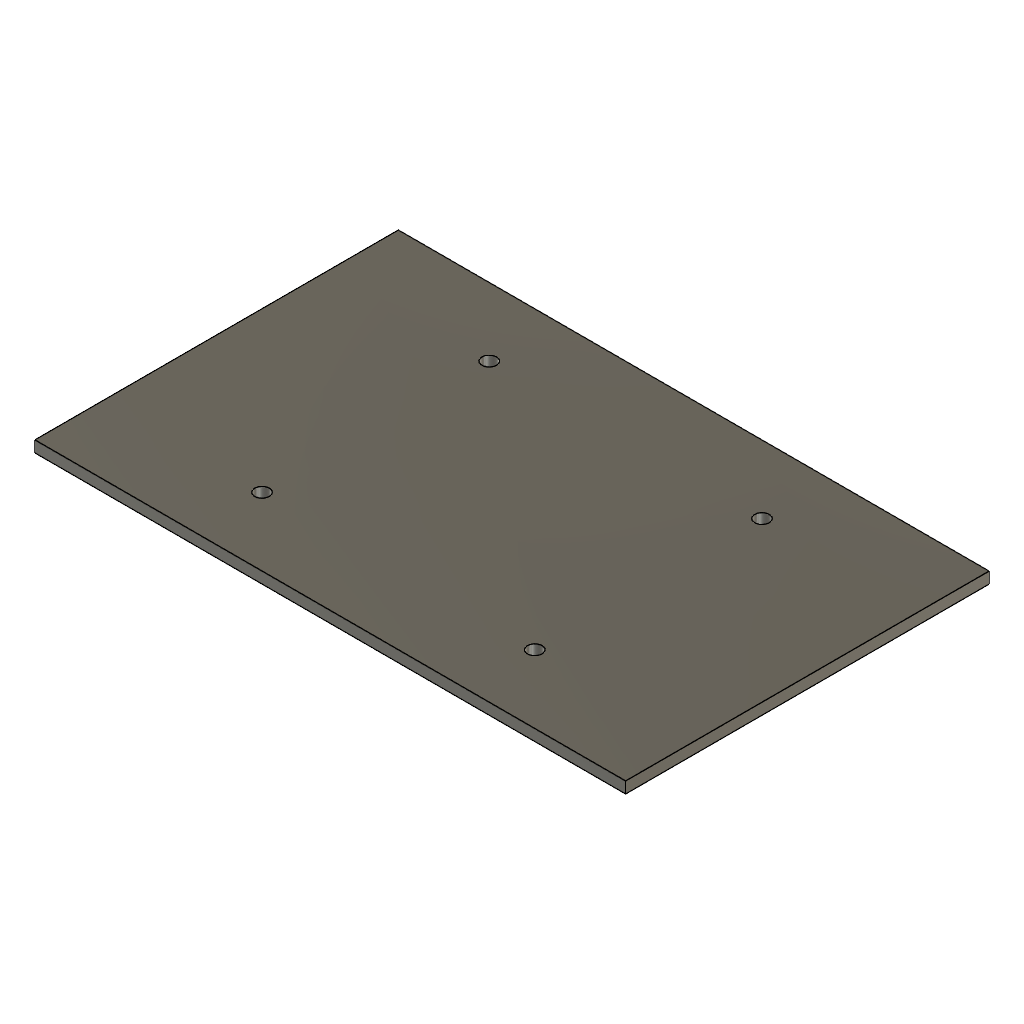
Controlled Traffic System - Vehicle Unit (Autodesk Fusion 360 archive; units mm, degrees)
design "Mounting Deck"
part number: 2026-10-08-00-01-35-748
Autodesk Fusion 360 part; units mm, degrees
ref_plane "WorkPlane2" through (0, 0, 28) normal (0, 0, 1) x (1, 0, 0)
sketch "01 - Enlarged Mounting Deck Profile" plane through (0, 0, 28) normal (0, 0, 1) x (1, 0, 0)
  line L0 (-65, -40) -> (65, -40)
  line L1 (65, -40) -> (65, 40)
  line L2 (65, 40) -> (-65, 40)
  line L3 (-65, 40) -> (-65, -40)
  circle A0 centre (-30, -25) radius 1.6
  circle A1 centre (30, -25) radius 1.6
  circle A2 centre (-30, 25) radius 1.6
  circle A3 centre (30, 25) radius 1.6
extrude "02 - Enlarged Mounting Deck" add sketch "01 - Enlarged Mounting Deck Profile" along normal blind 2.5

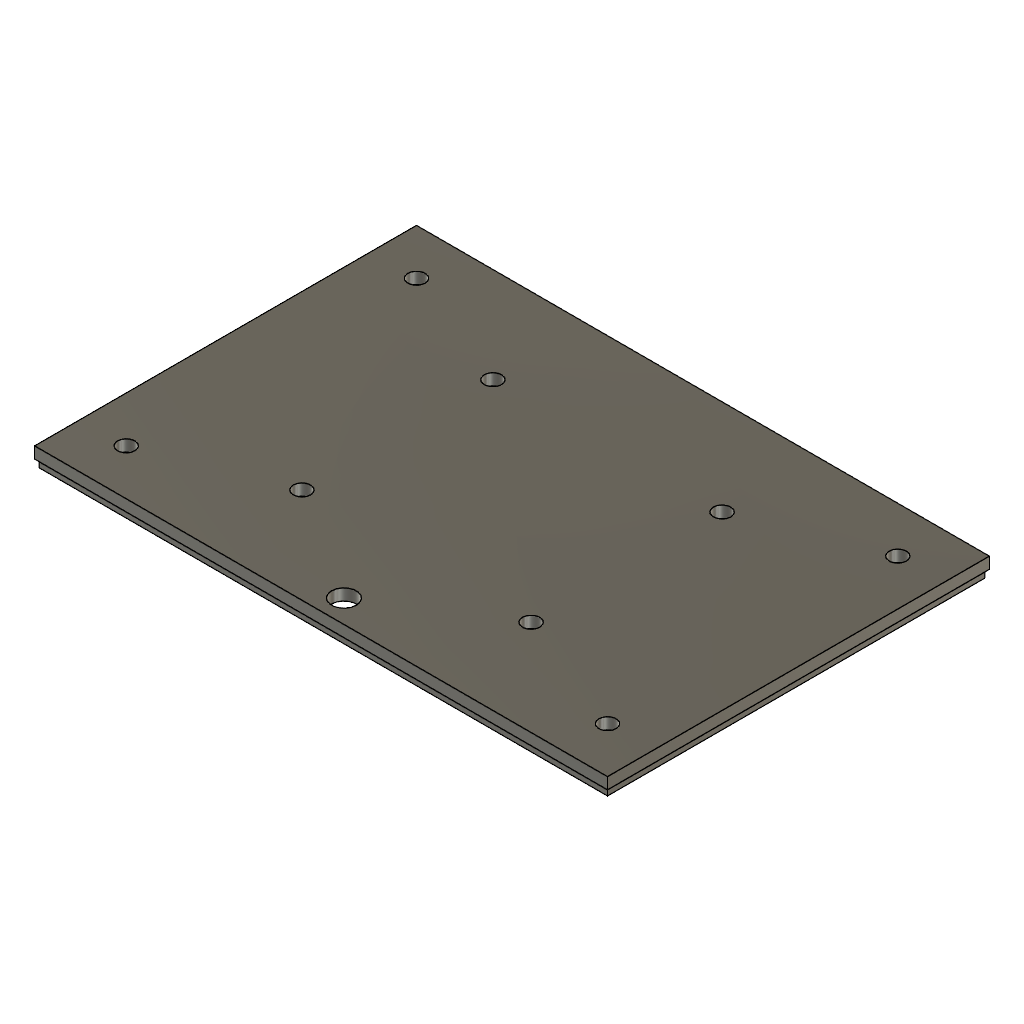
design "Enclosure Lid"
part number: 2026-10-07-13-07-07-370
Autodesk Fusion 360 part; units mm, degrees
ref_plane "WorkPlane1" through (0, 0, 32) normal (0, 0, 1) x (1, 0, 0)
sketch "01 - Lid Base Sketch" plane through (0, 0, 32) normal (0, 0, 1) x (1, 0, 0)
  line L0 (-75, -50) -> (75, -50)
  line L1 (75, -50) -> (75, 50)
  line L2 (75, 50) -> (-75, 50)
  line L3 (-75, 50) -> (-75, -50)
extrude "02 - Lid Plate" add sketch "01 - Lid Base Sketch" along normal blind 3
sketch "03 - Lid Seating Lip Sketch" plane through (0, 0, 32) normal (0, 0, 1) x (1, 0, 0)
  line L0 (-74.4, -49.4) -> (74.4, -49.4)
  line L1 (74.4, -49.4) -> (74.4, 49.4)
  line L2 (74.4, 49.4) -> (-74.4, 49.4)
  line L3 (-74.4, 49.4) -> (-74.4, -49.4)
  line L4 (-72.4, -47.4) -> (72.4, -47.4)
  line L5 (72.4, -47.4) -> (72.4, 47.4)
  line L6 (72.4, 47.4) -> (-72.4, 47.4)
  line L7 (-72.4, 47.4) -> (-72.4, -47.4)
extrude "04 - Lid Seating Lip" add sketch "03 - Lid Seating Lip Sketch" against normal blind 2
sketch "05 - Lid Screw Holes 8 Positions" plane through (0, 0, 32) normal (0, 0, 1) x (1, 0, 0)
  circle A0 centre (-63, -38) radius 2.25
  circle A1 centre (63, -38) radius 2.25
  circle A2 centre (-30, -25) radius 2.25
  circle A3 centre (30, -25) radius 2.25
  circle A4 centre (-30, 25) radius 2.25
  circle A5 centre (30, 25) radius 2.25
  circle A6 centre (-63, 38) radius 2.25
  circle A7 centre (63, 38) radius 2.25
extrude "06 - Lid Screw Hole 1" cut sketch "05 - Lid Screw Holes 8 Positions" along normal blind 3 contours A0
extrude "06 - Lid Screw Hole 2" cut sketch "05 - Lid Screw Holes 8 Positions" along normal blind 3 contours A4
extrude "06 - Lid Screw Hole 3" cut sketch "05 - Lid Screw Holes 8 Positions" along normal blind 3 contours A3
extrude "06 - Lid Screw Hole 4" cut sketch "05 - Lid Screw Holes 8 Positions" along normal blind 3 contours A5
extrude "06 - Lid Screw Hole 5" cut sketch "05 - Lid Screw Holes 8 Positions" along normal blind 3 contours A2
extrude "06 - Lid Screw Hole 6" cut sketch "05 - Lid Screw Holes 8 Positions" along normal blind 3 contours A6
extrude "06 - Lid Screw Hole 7" cut sketch "05 - Lid Screw Holes 8 Positions" along normal blind 3 contours A1
extrude "06 - Lid Screw Hole 8" cut sketch "05 - Lid Screw Holes 8 Positions" along normal blind 3 contours A7
sketch "07 - Cellular Antenna Hole" plane through (0, 0, 32) normal (0, 0, 1) x (1, 0, 0)
  circle A0 centre (0, -44) radius 3.25
extrude "08 - Cellular Antenna Pass-Through" cut sketch "07 - Cellular Antenna Hole" along normal blind 3

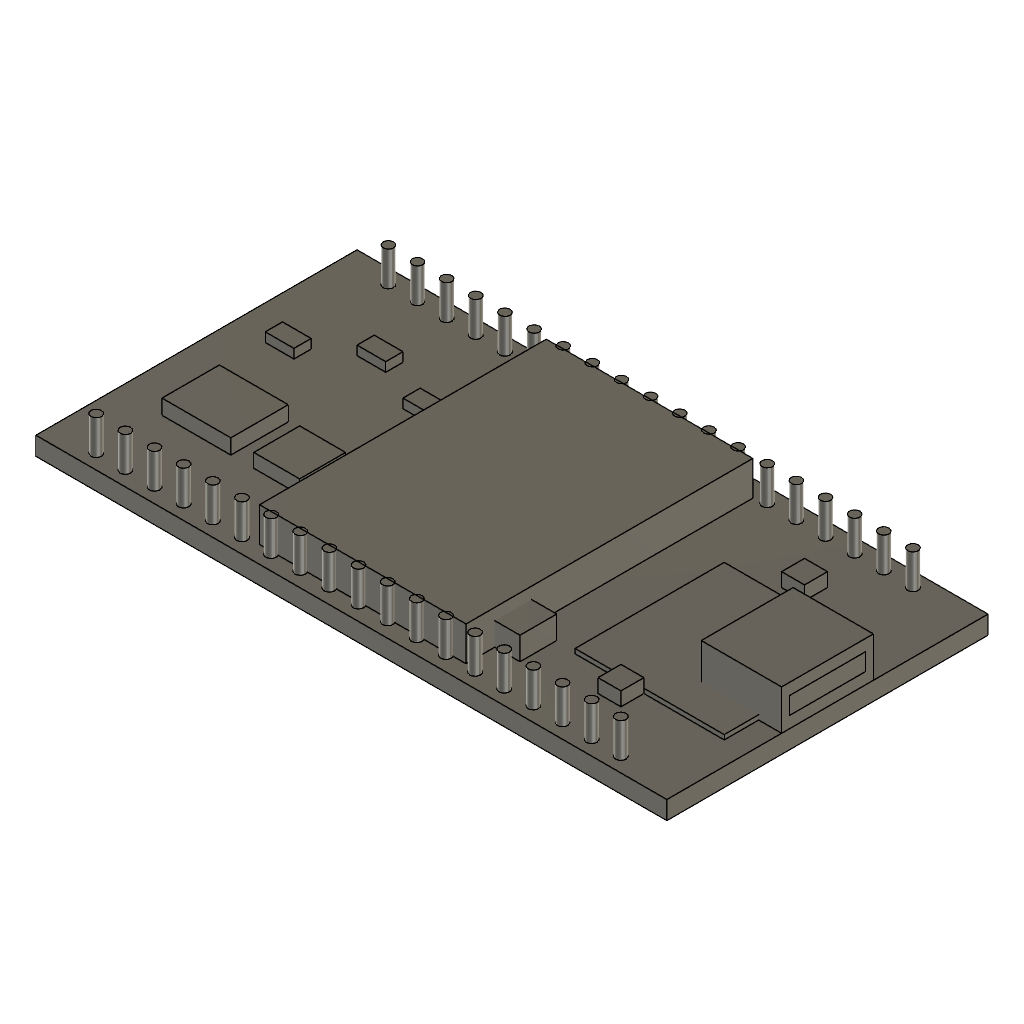
design "ESP32"
part number: 2026-10-08-00-19-46-799
Autodesk Fusion 360 part; units mm, degrees
ref_plane "WorkPlane1" through (0, 0, 30.5) normal (0, 0, 1) x (1, 0, 0)
sketch "01 - ESP32 DevKitC V4 PCB Sketch" plane through (0, 0, 30.5) normal (0, 0, 1) x (1, 0, 0)
  line L0 (-34.5, -9) -> (20.5, -9)
  line L1 (20.5, -9) -> (20.5, 19)
  line L2 (20.5, 19) -> (-34.5, 19)
  line L3 (-34.5, 19) -> (-34.5, -9)
extrude "01 - ESP32 DevKitC V4 PCB" add sketch "01 - ESP32 DevKitC V4 PCB Sketch" along normal blind 1.6 makes body 1
ref_plane "WorkPlane2" through (0, 0, 32.1) normal (0, 0, 1) x (1, 0, 0)
sketch "02 - ESP32-WROOM-32E Shield Sketch" plane through (0, 0, 32.1) normal (0, 0, 1) x (1, 0, 0)
  line L0 (-16.5, -7.5) -> (1.5, -7.5)
  line L1 (1.5, -7.5) -> (1.5, 17.5)
  line L2 (1.5, 17.5) -> (-16.5, 17.5)
  line L3 (-16.5, 17.5) -> (-16.5, -7.5)
extrude "02 - ESP32-WROOM-32E Shield" add sketch "02 - ESP32-WROOM-32E Shield Sketch" along normal blind 3 separate body makes body 2
ref_plane "WorkPlane3" through (0, 0, 32.1) normal (0, 0, 1) x (1, 0, 0)
sketch "Left Header Pin 01" plane through (0, 0, 32.1) normal (0, 0, 1) x (1, 0, 0)
  circle A0 centre (-30.5, -7.73) radius 0.45
extrude "03 - Left Header Pin 01" add sketch "Left Header Pin 01" along normal blind 3 separate body makes body 3
ref_plane "WorkPlane4" through (0, 0, 32.1) normal (0, 0, 1) x (1, 0, 0)
sketch "Left Header Pin 02" plane through (0, 0, 32.1) normal (0, 0, 1) x (1, 0, 0)
  circle A0 centre (-27.96, -7.73) radius 0.45
extrude "03 - Left Header Pin 02" add sketch "Left Header Pin 02" along normal blind 3 separate body makes body 4
ref_plane "WorkPlane5" through (0, 0, 32.1) normal (0, 0, 1) x (1, 0, 0)
sketch "Left Header Pin 03" plane through (0, 0, 32.1) normal (0, 0, 1) x (1, 0, 0)
  circle A0 centre (-25.42, -7.73) radius 0.45
extrude "03 - Left Header Pin 03" add sketch "Left Header Pin 03" along normal blind 3 separate body makes body 5
ref_plane "WorkPlane6" through (0, 0, 32.1) normal (0, 0, 1) x (1, 0, 0)
sketch "Left Header Pin 04" plane through (0, 0, 32.1) normal (0, 0, 1) x (1, 0, 0)
  circle A0 centre (-22.88, -7.73) radius 0.45
extrude "03 - Left Header Pin 04" add sketch "Left Header Pin 04" along normal blind 3 separate body makes body 6
ref_plane "WorkPlane7" through (0, 0, 32.1) normal (0, 0, 1) x (1, 0, 0)
sketch "Left Header Pin 05" plane through (0, 0, 32.1) normal (0, 0, 1) x (1, 0, 0)
  circle A0 centre (-20.34, -7.73) radius 0.45
extrude "03 - Left Header Pin 05" add sketch "Left Header Pin 05" along normal blind 3 separate body makes body 7
ref_plane "WorkPlane8" through (0, 0, 32.1) normal (0, 0, 1) x (1, 0, 0)
sketch "Left Header Pin 06" plane through (0, 0, 32.1) normal (0, 0, 1) x (1, 0, 0)
  circle A0 centre (-17.8, -7.73) radius 0.45
extrude "03 - Left Header Pin 06" add sketch "Left Header Pin 06" along normal blind 3 separate body makes body 8
ref_plane "WorkPlane9" through (0, 0, 32.1) normal (0, 0, 1) x (1, 0, 0)
sketch "Left Header Pin 07" plane through (0, 0, 32.1) normal (0, 0, 1) x (1, 0, 0)
  circle A0 centre (-15.26, -7.73) radius 0.45
extrude "03 - Left Header Pin 07" add sketch "Left Header Pin 07" along normal blind 3 separate body makes body 9
ref_plane "WorkPlane10" through (0, 0, 32.1) normal (0, 0, 1) x (1, 0, 0)
sketch "Left Header Pin 08" plane through (0, 0, 32.1) normal (0, 0, 1) x (1, 0, 0)
  circle A0 centre (-12.72, -7.73) radius 0.45
extrude "03 - Left Header Pin 08" add sketch "Left Header Pin 08" along normal blind 3 separate body makes body 10
ref_plane "WorkPlane11" through (0, 0, 32.1) normal (0, 0, 1) x (1, 0, 0)
sketch "Left Header Pin 09" plane through (0, 0, 32.1) normal (0, 0, 1) x (1, 0, 0)
  circle A0 centre (-10.18, -7.73) radius 0.45
extrude "03 - Left Header Pin 09" add sketch "Left Header Pin 09" along normal blind 3 separate body makes body 11
ref_plane "WorkPlane12" through (0, 0, 32.1) normal (0, 0, 1) x (1, 0, 0)
sketch "Left Header Pin 10" plane through (0, 0, 32.1) normal (0, 0, 1) x (1, 0, 0)
  circle A0 centre (-7.64, -7.73) radius 0.45
extrude "03 - Left Header Pin 10" add sketch "Left Header Pin 10" along normal blind 3 separate body makes body 12
ref_plane "WorkPlane13" through (0, 0, 32.1) normal (0, 0, 1) x (1, 0, 0)
sketch "Left Header Pin 11" plane through (0, 0, 32.1) normal (0, 0, 1) x (1, 0, 0)
  circle A0 centre (-5.1, -7.73) radius 0.45
extrude "03 - Left Header Pin 11" add sketch "Left Header Pin 11" along normal blind 3 separate body makes body 13
ref_plane "WorkPlane14" through (0, 0, 32.1) normal (0, 0, 1) x (1, 0, 0)
sketch "Left Header Pin 12" plane through (0, 0, 32.1) normal (0, 0, 1) x (1, 0, 0)
  circle A0 centre (-2.56, -7.73) radius 0.45
extrude "03 - Left Header Pin 12" add sketch "Left Header Pin 12" along normal blind 3 separate body makes body 14
ref_plane "WorkPlane15" through (0, 0, 32.1) normal (0, 0, 1) x (1, 0, 0)
sketch "Left Header Pin 13" plane through (0, 0, 32.1) normal (0, 0, 1) x (1, 0, 0)
  circle A0 centre (-0.02, -7.73) radius 0.45
extrude "03 - Left Header Pin 13" add sketch "Left Header Pin 13" along normal blind 3 separate body makes body 15
ref_plane "WorkPlane16" through (0, 0, 32.1) normal (0, 0, 1) x (1, 0, 0)
sketch "Left Header Pin 14" plane through (0, 0, 32.1) normal (0, 0, 1) x (1, 0, 0)
  circle A0 centre (2.52, -7.73) radius 0.45
extrude "03 - Left Header Pin 14" add sketch "Left Header Pin 14" along normal blind 3 separate body makes body 16
ref_plane "WorkPlane17" through (0, 0, 32.1) normal (0, 0, 1) x (1, 0, 0)
sketch "Left Header Pin 15" plane through (0, 0, 32.1) normal (0, 0, 1) x (1, 0, 0)
  circle A0 centre (5.06, -7.73) radius 0.45
extrude "03 - Left Header Pin 15" add sketch "Left Header Pin 15" along normal blind 3 separate body makes body 17
ref_plane "WorkPlane18" through (0, 0, 32.1) normal (0, 0, 1) x (1, 0, 0)
sketch "Left Header Pin 16" plane through (0, 0, 32.1) normal (0, 0, 1) x (1, 0, 0)
  circle A0 centre (7.6, -7.73) radius 0.45
extrude "03 - Left Header Pin 16" add sketch "Left Header Pin 16" along normal blind 3 separate body makes body 18
ref_plane "WorkPlane19" through (0, 0, 32.1) normal (0, 0, 1) x (1, 0, 0)
sketch "Left Header Pin 17" plane through (0, 0, 32.1) normal (0, 0, 1) x (1, 0, 0)
  circle A0 centre (10.14, -7.73) radius 0.45
extrude "03 - Left Header Pin 17" add sketch "Left Header Pin 17" along normal blind 3 separate body makes body 19
ref_plane "WorkPlane20" through (0, 0, 32.1) normal (0, 0, 1) x (1, 0, 0)
sketch "Left Header Pin 18" plane through (0, 0, 32.1) normal (0, 0, 1) x (1, 0, 0)
  circle A0 centre (12.68, -7.73) radius 0.45
extrude "03 - Left Header Pin 18" add sketch "Left Header Pin 18" along normal blind 3 separate body makes body 20
ref_plane "WorkPlane21" through (0, 0, 32.1) normal (0, 0, 1) x (1, 0, 0)
sketch "Left Header Pin 19" plane through (0, 0, 32.1) normal (0, 0, 1) x (1, 0, 0)
  circle A0 centre (15.22, -7.73) radius 0.45
extrude "03 - Left Header Pin 19" add sketch "Left Header Pin 19" along normal blind 3 separate body makes body 21
ref_plane "WorkPlane22" through (0, 0, 32.1) normal (0, 0, 1) x (1, 0, 0)
sketch "Right Header Pin 01" plane through (0, 0, 32.1) normal (0, 0, 1) x (1, 0, 0)
  circle A0 centre (-30.5, 17.73) radius 0.45
extrude "04 - Right Header Pin 01" add sketch "Right Header Pin 01" along normal blind 3 separate body makes body 22
ref_plane "WorkPlane23" through (0, 0, 32.1) normal (0, 0, 1) x (1, 0, 0)
sketch "Right Header Pin 02" plane through (0, 0, 32.1) normal (0, 0, 1) x (1, 0, 0)
  circle A0 centre (-27.96, 17.73) radius 0.45
extrude "04 - Right Header Pin 02" add sketch "Right Header Pin 02" along normal blind 3 separate body makes body 23
ref_plane "WorkPlane24" through (0, 0, 32.1) normal (0, 0, 1) x (1, 0, 0)
sketch "Right Header Pin 03" plane through (0, 0, 32.1) normal (0, 0, 1) x (1, 0, 0)
  circle A0 centre (-25.42, 17.73) radius 0.45
extrude "04 - Right Header Pin 03" add sketch "Right Header Pin 03" along normal blind 3 separate body makes body 24
ref_plane "WorkPlane25" through (0, 0, 32.1) normal (0, 0, 1) x (1, 0, 0)
sketch "Right Header Pin 04" plane through (0, 0, 32.1) normal (0, 0, 1) x (1, 0, 0)
  circle A0 centre (-22.88, 17.73) radius 0.45
extrude "04 - Right Header Pin 04" add sketch "Right Header Pin 04" along normal blind 3 separate body makes body 25
ref_plane "WorkPlane26" through (0, 0, 32.1) normal (0, 0, 1) x (1, 0, 0)
sketch "Right Header Pin 05" plane through (0, 0, 32.1) normal (0, 0, 1) x (1, 0, 0)
  circle A0 centre (-20.34, 17.73) radius 0.45
extrude "04 - Right Header Pin 05" add sketch "Right Header Pin 05" along normal blind 3 separate body makes body 26
ref_plane "WorkPlane27" through (0, 0, 32.1) normal (0, 0, 1) x (1, 0, 0)
sketch "Right Header Pin 06" plane through (0, 0, 32.1) normal (0, 0, 1) x (1, 0, 0)
  circle A0 centre (-17.8, 17.73) radius 0.45
extrude "04 - Right Header Pin 06" add sketch "Right Header Pin 06" along normal blind 3 separate body makes body 27
ref_plane "WorkPlane28" through (0, 0, 32.1) normal (0, 0, 1) x (1, 0, 0)
sketch "Right Header Pin 07" plane through (0, 0, 32.1) normal (0, 0, 1) x (1, 0, 0)
  circle A0 centre (-15.26, 17.73) radius 0.45
extrude "04 - Right Header Pin 07" add sketch "Right Header Pin 07" along normal blind 3 separate body makes body 28
ref_plane "WorkPlane29" through (0, 0, 32.1) normal (0, 0, 1) x (1, 0, 0)
sketch "Right Header Pin 08" plane through (0, 0, 32.1) normal (0, 0, 1) x (1, 0, 0)
  circle A0 centre (-12.72, 17.73) radius 0.45
extrude "04 - Right Header Pin 08" add sketch "Right Header Pin 08" along normal blind 3 separate body makes body 29
ref_plane "WorkPlane30" through (0, 0, 32.1) normal (0, 0, 1) x (1, 0, 0)
sketch "Right Header Pin 09" plane through (0, 0, 32.1) normal (0, 0, 1) x (1, 0, 0)
  circle A0 centre (-10.18, 17.73) radius 0.45
extrude "04 - Right Header Pin 09" add sketch "Right Header Pin 09" along normal blind 3 separate body makes body 30
ref_plane "WorkPlane31" through (0, 0, 32.1) normal (0, 0, 1) x (1, 0, 0)
sketch "Right Header Pin 10" plane through (0, 0, 32.1) normal (0, 0, 1) x (1, 0, 0)
  circle A0 centre (-7.64, 17.73) radius 0.45
extrude "04 - Right Header Pin 10" add sketch "Right Header Pin 10" along normal blind 3 separate body makes body 31
ref_plane "WorkPlane32" through (0, 0, 32.1) normal (0, 0, 1) x (1, 0, 0)
sketch "Right Header Pin 11" plane through (0, 0, 32.1) normal (0, 0, 1) x (1, 0, 0)
  circle A0 centre (-5.1, 17.73) radius 0.45
extrude "04 - Right Header Pin 11" add sketch "Right Header Pin 11" along normal blind 3 separate body makes body 32
ref_plane "WorkPlane33" through (0, 0, 32.1) normal (0, 0, 1) x (1, 0, 0)
sketch "Right Header Pin 12" plane through (0, 0, 32.1) normal (0, 0, 1) x (1, 0, 0)
  circle A0 centre (-2.56, 17.73) radius 0.45
extrude "04 - Right Header Pin 12" add sketch "Right Header Pin 12" along normal blind 3 separate body makes body 33
ref_plane "WorkPlane34" through (0, 0, 32.1) normal (0, 0, 1) x (1, 0, 0)
sketch "Right Header Pin 13" plane through (0, 0, 32.1) normal (0, 0, 1) x (1, 0, 0)
  circle A0 centre (-0.02, 17.73) radius 0.45
extrude "04 - Right Header Pin 13" add sketch "Right Header Pin 13" along normal blind 3 separate body makes body 34
ref_plane "WorkPlane35" through (0, 0, 32.1) normal (0, 0, 1) x (1, 0, 0)
sketch "Right Header Pin 14" plane through (0, 0, 32.1) normal (0, 0, 1) x (1, 0, 0)
  circle A0 centre (2.52, 17.73) radius 0.45
extrude "04 - Right Header Pin 14" add sketch "Right Header Pin 14" along normal blind 3 separate body makes body 35
ref_plane "WorkPlane36" through (0, 0, 32.1) normal (0, 0, 1) x (1, 0, 0)
sketch "Right Header Pin 15" plane through (0, 0, 32.1) normal (0, 0, 1) x (1, 0, 0)
  circle A0 centre (5.06, 17.73) radius 0.45
extrude "04 - Right Header Pin 15" add sketch "Right Header Pin 15" along normal blind 3 separate body makes body 36
ref_plane "WorkPlane37" through (0, 0, 32.1) normal (0, 0, 1) x (1, 0, 0)
sketch "Right Header Pin 16" plane through (0, 0, 32.1) normal (0, 0, 1) x (1, 0, 0)
  circle A0 centre (7.6, 17.73) radius 0.45
extrude "04 - Right Header Pin 16" add sketch "Right Header Pin 16" along normal blind 3 separate body makes body 37
ref_plane "WorkPlane38" through (0, 0, 32.1) normal (0, 0, 1) x (1, 0, 0)
sketch "Right Header Pin 17" plane through (0, 0, 32.1) normal (0, 0, 1) x (1, 0, 0)
  circle A0 centre (10.14, 17.73) radius 0.45
extrude "04 - Right Header Pin 17" add sketch "Right Header Pin 17" along normal blind 3 separate body makes body 38
ref_plane "WorkPlane39" through (0, 0, 32.1) normal (0, 0, 1) x (1, 0, 0)
sketch "Right Header Pin 18" plane through (0, 0, 32.1) normal (0, 0, 1) x (1, 0, 0)
  circle A0 centre (12.68, 17.73) radius 0.45
extrude "04 - Right Header Pin 18" add sketch "Right Header Pin 18" along normal blind 3 separate body makes body 39
ref_plane "WorkPlane40" through (0, 0, 32.1) normal (0, 0, 1) x (1, 0, 0)
sketch "Right Header Pin 19" plane through (0, 0, 32.1) normal (0, 0, 1) x (1, 0, 0)
  circle A0 centre (15.22, 17.73) radius 0.45
extrude "04 - Right Header Pin 19" add sketch "Right Header Pin 19" along normal blind 3 separate body makes body 40
ref_plane "WorkPlane41" through (0, 0, 32.1) normal (0, 0, 1) x (1, 0, 0)
sketch "05 - Micro USB Connector Sketch" plane through (0, 0, 32.1) normal (0, 0, 1) x (1, 0, 0)
  line L0 (13.5, 1) -> (20.5, 1)
  line L1 (20.5, 1) -> (20.5, 9)
  line L2 (20.5, 9) -> (13.5, 9)
  line L3 (13.5, 9) -> (13.5, 1)
extrude "05 - Micro USB Connector" add sketch "05 - Micro USB Connector Sketch" along normal blind 3.5 separate body makes body 41
ref_plane "WorkPlane42" through (0, 0, 33.1) normal (0, 0, 1) x (1, 0, 0)
sketch "06 - USB Connector Shield Sketch" plane through (0, 0, 33.1) normal (0, 0, 1) x (1, 0, 0)
  line L0 (14.3, 1.7) -> (20.5, 1.7)
  line L1 (20.5, 1.7) -> (20.5, 8.3)
  line L2 (20.5, 8.3) -> (14.3, 8.3)
  line L3 (14.3, 8.3) -> (14.3, 1.7)
extrude "06 - USB Connector Shield" add sketch "06 - USB Connector Shield Sketch" along normal blind 1.5 separate body makes body 42
ref_plane "WorkPlane43" through (0, 0, 32.1) normal (0, 0, 1) x (1, 0, 0)
sketch "07 - EN Button Sketch" plane through (0, 0, 32.1) normal (0, 0, 1) x (1, 0, 0)
  line L0 (-5.5, -5) -> (-2.3, -5)
  line L1 (-2.3, -5) -> (-2.3, -1.8)
  line L2 (-2.3, -1.8) -> (-5.5, -1.8)
  line L3 (-5.5, -1.8) -> (-5.5, -5)
extrude "07 - EN Button" add sketch "07 - EN Button Sketch" along normal blind 2 separate body makes body 43
ref_plane "WorkPlane44" through (0, 0, 32.1) normal (0, 0, 1) x (1, 0, 0)
sketch "08 - BOOT Button Sketch" plane through (0, 0, 32.1) normal (0, 0, 1) x (1, 0, 0)
  line L0 (0.5, -5) -> (3.7, -5)
  line L1 (3.7, -5) -> (3.7, -1.8)
  line L2 (3.7, -1.8) -> (0.5, -1.8)
  line L3 (0.5, -1.8) -> (0.5, -5)
extrude "08 - BOOT Button" add sketch "08 - BOOT Button Sketch" along normal blind 2 separate body makes body 44
ref_plane "WorkPlane45" through (0, 0, 32.1) normal (0, 0, 1) x (1, 0, 0)
sketch "09 - USB UART IC Sketch" plane through (0, 0, 32.1) normal (0, 0, 1) x (1, 0, 0)
  line L0 (-30.5, -2) -> (-24.5, -2)
  line L1 (-24.5, -2) -> (-24.5, 3)
  line L2 (-24.5, 3) -> (-30.5, 3)
  line L3 (-30.5, 3) -> (-30.5, -2)
extrude "09 - USB UART IC" add sketch "09 - USB UART IC Sketch" along normal blind 1.3 separate body makes body 45
ref_plane "WorkPlane46" through (0, 0, 32.1) normal (0, 0, 1) x (1, 0, 0)
sketch "10 - Support IC Sketch" plane through (0, 0, 32.1) normal (0, 0, 1) x (1, 0, 0)
  line L0 (-22.5, -2) -> (-18.5, -2)
  line L1 (-18.5, -2) -> (-18.5, 2)
  line L2 (-18.5, 2) -> (-22.5, 2)
  line L3 (-22.5, 2) -> (-22.5, -2)
extrude "10 - Support IC" add sketch "10 - Support IC Sketch" along normal blind 1.2 separate body makes body 46
ref_plane "WorkPlane47" through (0, 0, 32.1) normal (0, 0, 1) x (1, 0, 0)
sketch "11 - Status LED Sketch" plane through (0, 0, 32.1) normal (0, 0, 1) x (1, 0, 0)
  line L0 (9.5, -4) -> (11.5, -4)
  line L1 (11.5, -4) -> (11.5, -2)
  line L2 (11.5, -2) -> (9.5, -2)
  line L3 (9.5, -2) -> (9.5, -4)
extrude "11 - Status LED" add sketch "11 - Status LED Sketch" along normal blind 1.2 separate body makes body 47
ref_plane "WorkPlane48" through (0, 0, 32.1) normal (0, 0, 1) x (1, 0, 0)
sketch "12 - Power LED Sketch" plane through (0, 0, 32.1) normal (0, 0, 1) x (1, 0, 0)
  line L0 (9.5, 12) -> (11.5, 12)
  line L1 (11.5, 12) -> (11.5, 14)
  line L2 (11.5, 14) -> (9.5, 14)
  line L3 (9.5, 14) -> (9.5, 12)
extrude "12 - Power LED" add sketch "12 - Power LED Sketch" along normal blind 1.2 separate body makes body 48
ref_plane "WorkPlane49" through (0, 0, 32.1) normal (0, 0, 1) x (1, 0, 0)
sketch "13 - PCB Antenna Area Sketch" plane through (0, 0, 32.1) normal (0, 0, 1) x (1, 0, 0)
  line L0 (5.5, -2) -> (18.5, -2)
  line L1 (18.5, -2) -> (18.5, 11)
  line L2 (18.5, 11) -> (5.5, 11)
  line L3 (5.5, 11) -> (5.5, -2)
extrude "13 - PCB Antenna Area" add sketch "13 - PCB Antenna Area Sketch" along normal blind 0.4 separate body makes body 49
ref_plane "WorkPlane50" through (0, 0, 32.1) normal (0, 0, 1) x (1, 0, 0)
sketch "14 - SMD Component 01 Sketch" plane through (0, 0, 32.1) normal (0, 0, 1) x (1, 0, 0)
  line L0 (-31.5, 8) -> (-29, 8)
  line L1 (-29, 8) -> (-29, 9.5)
  line L2 (-29, 9.5) -> (-31.5, 9.5)
  line L3 (-31.5, 9.5) -> (-31.5, 8)
extrude "14 - SMD Component 01" add sketch "14 - SMD Component 01 Sketch" along normal blind 0.8 separate body makes body 50
ref_plane "WorkPlane51" through (0, 0, 32.1) normal (0, 0, 1) x (1, 0, 0)
sketch "14 - SMD Component 02 Sketch" plane through (0, 0, 32.1) normal (0, 0, 1) x (1, 0, 0)
  line L0 (-26.5, 11) -> (-24, 11)
  line L1 (-24, 11) -> (-24, 12.5)
  line L2 (-24, 12.5) -> (-26.5, 12.5)
  line L3 (-26.5, 12.5) -> (-26.5, 11)
extrude "14 - SMD Component 02" add sketch "14 - SMD Component 02 Sketch" along normal blind 0.8 separate body makes body 51
ref_plane "WorkPlane52" through (0, 0, 32.1) normal (0, 0, 1) x (1, 0, 0)
sketch "14 - SMD Component 03 Sketch" plane through (0, 0, 32.1) normal (0, 0, 1) x (1, 0, 0)
  line L0 (-20.5, 9) -> (-18, 9)
  line L1 (-18, 9) -> (-18, 10.5)
  line L2 (-18, 10.5) -> (-20.5, 10.5)
  line L3 (-20.5, 10.5) -> (-20.5, 9)
extrude "14 - SMD Component 03" add sketch "14 - SMD Component 03 Sketch" along normal blind 0.8 separate body makes body 52
ref_plane "WorkPlane53" through (0, 0, 32.1) normal (0, 0, 1) x (1, 0, 0)
sketch "14 - SMD Component 04 Sketch" plane through (0, 0, 32.1) normal (0, 0, 1) x (1, 0, 0)
  line L0 (-14.5, 11) -> (-12, 11)
  line L1 (-12, 11) -> (-12, 12.5)
  line L2 (-12, 12.5) -> (-14.5, 12.5)
  line L3 (-14.5, 12.5) -> (-14.5, 11)
extrude "14 - SMD Component 04" add sketch "14 - SMD Component 04 Sketch" along normal blind 0.8 separate body makes body 53
ref_plane "WorkPlane54" through (0, 0, 32.1) normal (0, 0, 1) x (1, 0, 0)
sketch "14 - SMD Component 05 Sketch" plane through (0, 0, 32.1) normal (0, 0, 1) x (1, 0, 0)
  line L0 (-8.5, 9) -> (-6, 9)
  line L1 (-6, 9) -> (-6, 10.5)
  line L2 (-6, 10.5) -> (-8.5, 10.5)
  line L3 (-8.5, 10.5) -> (-8.5, 9)
extrude "14 - SMD Component 05" add sketch "14 - SMD Component 05 Sketch" along normal blind 0.8 separate body makes body 54
ref_plane "WorkPlane55" through (0, 0, 32.1) normal (0, 0, 1) x (1, 0, 0)
sketch "14 - SMD Component 06 Sketch" plane through (0, 0, 32.1) normal (0, 0, 1) x (1, 0, 0)
  line L0 (-2.5, 12) -> (0, 12)
  line L1 (0, 12) -> (0, 13.5)
  line L2 (0, 13.5) -> (-2.5, 13.5)
  line L3 (-2.5, 13.5) -> (-2.5, 12)
extrude "14 - SMD Component 06" add sketch "14 - SMD Component 06 Sketch" along normal blind 0.8 separate body makes body 55

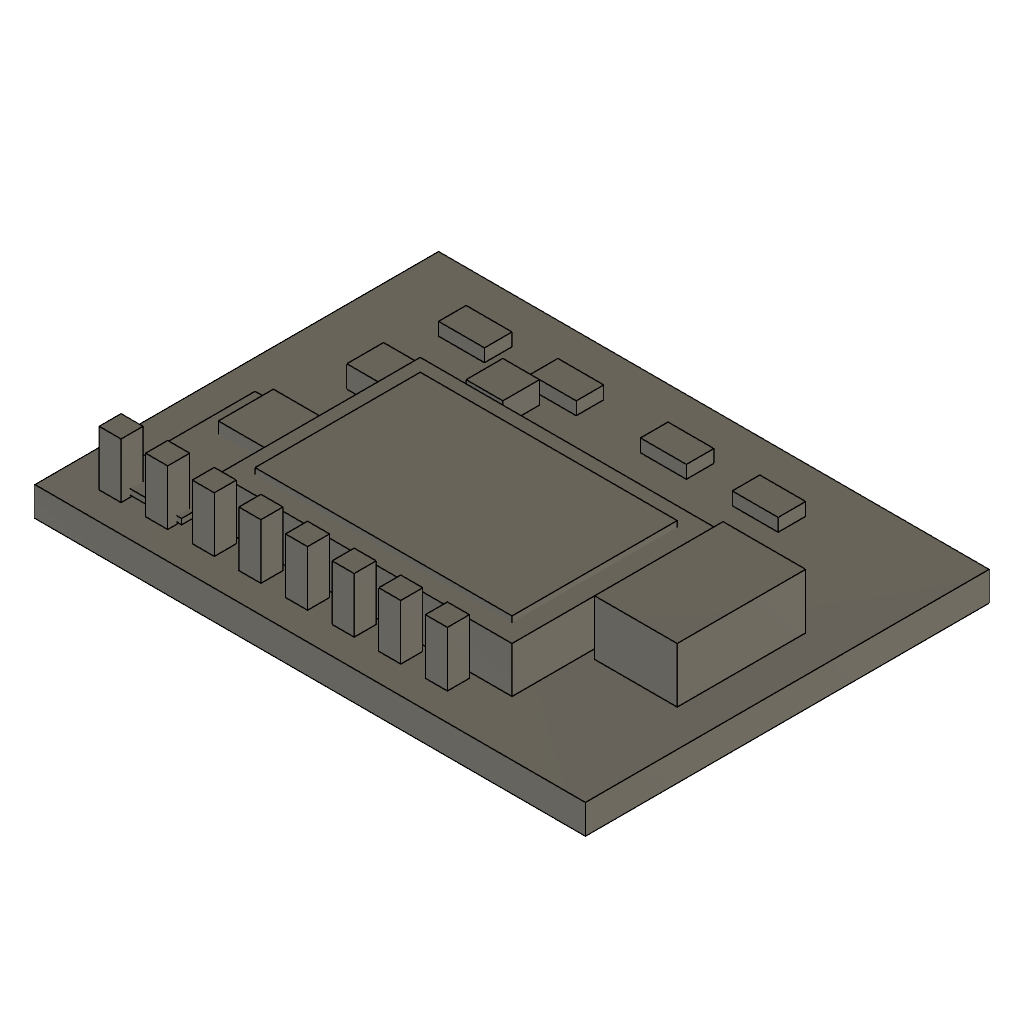
design "RTK GNSS"
part number: 2026-10-08-00-36-41-311
Autodesk Fusion 360 part; units mm, degrees
ref_plane "WorkPlane41" through (0, 0, 30.5) normal (0, 0, 1) x (1, 0, 0)
sketch "01 - RTK GNSS PCB Sketch" plane through (0, 0, 30.5) normal (0, 0, 1) x (1, 0, 0)
  line L0 (-10, -36) -> (20, -36)
  line L1 (20, -36) -> (20, -14)
  line L2 (20, -14) -> (-10, -14)
  line L3 (-10, -14) -> (-10, -36)
extrude "01 - RTK GNSS PCB" add sketch "01 - RTK GNSS PCB Sketch" along normal blind 1.6 makes body 1
ref_plane "WorkPlane42" through (0, 0, 32.1) normal (0, 0, 1) x (1, 0, 0)
sketch "02 - GNSS Receiver Sketch" plane through (0, 0, 32.1) normal (0, 0, 1) x (1, 0, 0)
  line L0 (-3, -33) -> (13, -33)
  line L1 (13, -33) -> (13, -22)
  line L2 (13, -22) -> (-3, -22)
  line L3 (-3, -22) -> (-3, -33)
extrude "02 - GNSS Receiver" add sketch "02 - GNSS Receiver Sketch" along normal blind 2.5 separate body makes body 2
ref_plane "WorkPlane43" through (0, 0, 34.1) normal (0, 0, 1) x (1, 0, 0)
sketch "03 - GNSS Shield Sketch" plane through (0, 0, 34.1) normal (0, 0, 1) x (1, 0, 0)
  line L0 (-2, -32) -> (12, -32)
  line L1 (12, -32) -> (12, -23)
  line L2 (12, -23) -> (-2, -23)
  line L3 (-2, -23) -> (-2, -32)
extrude "03 - GNSS Shield" add sketch "03 - GNSS Shield Sketch" along normal blind 0.8 separate body makes body 3
ref_plane "WorkPlane44" through (0, 0, 32.1) normal (0, 0, 1) x (1, 0, 0)
sketch "04 - GNSS Antenna Connector Sketch" plane through (0, 0, 32.1) normal (0, 0, 1) x (1, 0, 0)
  line L0 (13.5, -29) -> (18, -29)
  line L1 (18, -29) -> (18, -22)
  line L2 (18, -22) -> (13.5, -22)
  line L3 (13.5, -22) -> (13.5, -29)
extrude "04 - GNSS Antenna Connector" add sketch "04 - GNSS Antenna Connector Sketch" along normal blind 3 separate body makes body 4
ref_plane "WorkPlane45" through (0, 0, 32.1) normal (0, 0, 1) x (1, 0, 0)
sketch "05 - GNSS Header Pin 01 Sketch" plane through (0, 0, 32.1) normal (0, 0, 1) x (1, 0, 0)
  line L0 (-8, -34.5) -> (-6.8, -34.5)
  line L1 (-6.8, -34.5) -> (-6.8, -33.3)
  line L2 (-6.8, -33.3) -> (-8, -33.3)
  line L3 (-8, -33.3) -> (-8, -34.5)
extrude "05 - GNSS Header Pin 01" add sketch "05 - GNSS Header Pin 01 Sketch" along normal blind 3 separate body makes body 5
ref_plane "WorkPlane46" through (0, 0, 32.1) normal (0, 0, 1) x (1, 0, 0)
sketch "05 - GNSS Header Pin 02 Sketch" plane through (0, 0, 32.1) normal (0, 0, 1) x (1, 0, 0)
  line L0 (-5.46, -34.5) -> (-4.26, -34.5)
  line L1 (-4.26, -34.5) -> (-4.26, -33.3)
  line L2 (-4.26, -33.3) -> (-5.46, -33.3)
  line L3 (-5.46, -33.3) -> (-5.46, -34.5)
extrude "05 - GNSS Header Pin 02" add sketch "05 - GNSS Header Pin 02 Sketch" along normal blind 3 separate body makes body 6
ref_plane "WorkPlane47" through (0, 0, 32.1) normal (0, 0, 1) x (1, 0, 0)
sketch "05 - GNSS Header Pin 03 Sketch" plane through (0, 0, 32.1) normal (0, 0, 1) x (1, 0, 0)
  line L0 (-2.92, -34.5) -> (-1.72, -34.5)
  line L1 (-1.72, -34.5) -> (-1.72, -33.3)
  line L2 (-1.72, -33.3) -> (-2.92, -33.3)
  line L3 (-2.92, -33.3) -> (-2.92, -34.5)
extrude "05 - GNSS Header Pin 03" add sketch "05 - GNSS Header Pin 03 Sketch" along normal blind 3 separate body makes body 7
ref_plane "WorkPlane48" through (0, 0, 32.1) normal (0, 0, 1) x (1, 0, 0)
sketch "05 - GNSS Header Pin 04 Sketch" plane through (0, 0, 32.1) normal (0, 0, 1) x (1, 0, 0)
  line L0 (-0.38, -34.5) -> (0.82, -34.5)
  line L1 (0.82, -34.5) -> (0.82, -33.3)
  line L2 (0.82, -33.3) -> (-0.38, -33.3)
  line L3 (-0.38, -33.3) -> (-0.38, -34.5)
extrude "05 - GNSS Header Pin 04" add sketch "05 - GNSS Header Pin 04 Sketch" along normal blind 3 separate body makes body 8
ref_plane "WorkPlane49" through (0, 0, 32.1) normal (0, 0, 1) x (1, 0, 0)
sketch "05 - GNSS Header Pin 05 Sketch" plane through (0, 0, 32.1) normal (0, 0, 1) x (1, 0, 0)
  line L0 (2.16, -34.5) -> (3.36, -34.5)
  line L1 (3.36, -34.5) -> (3.36, -33.3)
  line L2 (3.36, -33.3) -> (2.16, -33.3)
  line L3 (2.16, -33.3) -> (2.16, -34.5)
extrude "05 - GNSS Header Pin 05" add sketch "05 - GNSS Header Pin 05 Sketch" along normal blind 3 separate body makes body 9
ref_plane "WorkPlane50" through (0, 0, 32.1) normal (0, 0, 1) x (1, 0, 0)
sketch "05 - GNSS Header Pin 06 Sketch" plane through (0, 0, 32.1) normal (0, 0, 1) x (1, 0, 0)
  line L0 (4.7, -34.5) -> (5.9, -34.5)
  line L1 (5.9, -34.5) -> (5.9, -33.3)
  line L2 (5.9, -33.3) -> (4.7, -33.3)
  line L3 (4.7, -33.3) -> (4.7, -34.5)
extrude "05 - GNSS Header Pin 06" add sketch "05 - GNSS Header Pin 06 Sketch" along normal blind 3 separate body makes body 10
ref_plane "WorkPlane51" through (0, 0, 32.1) normal (0, 0, 1) x (1, 0, 0)
sketch "05 - GNSS Header Pin 07 Sketch" plane through (0, 0, 32.1) normal (0, 0, 1) x (1, 0, 0)
  line L0 (7.24, -34.5) -> (8.44, -34.5)
  line L1 (8.44, -34.5) -> (8.44, -33.3)
  line L2 (8.44, -33.3) -> (7.24, -33.3)
  line L3 (7.24, -33.3) -> (7.24, -34.5)
extrude "05 - GNSS Header Pin 07" add sketch "05 - GNSS Header Pin 07 Sketch" along normal blind 3 separate body makes body 11
ref_plane "WorkPlane52" through (0, 0, 32.1) normal (0, 0, 1) x (1, 0, 0)
sketch "05 - GNSS Header Pin 08 Sketch" plane through (0, 0, 32.1) normal (0, 0, 1) x (1, 0, 0)
  line L0 (9.78, -34.5) -> (10.98, -34.5)
  line L1 (10.98, -34.5) -> (10.98, -33.3)
  line L2 (10.98, -33.3) -> (9.78, -33.3)
  line L3 (9.78, -33.3) -> (9.78, -34.5)
extrude "05 - GNSS Header Pin 08" add sketch "05 - GNSS Header Pin 08 Sketch" along normal blind 3 separate body makes body 12
ref_plane "WorkPlane53" through (0, 0, 32.1) normal (0, 0, 1) x (1, 0, 0)
sketch "06 - GNSS Status LED Sketch" plane through (0, 0, 32.1) normal (0, 0, 1) x (1, 0, 0)
  line L0 (-6, -23) -> (-4, -23)
  line L1 (-4, -23) -> (-4, -21)
  line L2 (-4, -21) -> (-6, -21)
  line L3 (-6, -21) -> (-6, -23)
extrude "06 - GNSS Status LED" add sketch "06 - GNSS Status LED Sketch" along normal blind 1.2 separate body makes body 13
ref_plane "WorkPlane54" through (0, 0, 32.1) normal (0, 0, 1) x (1, 0, 0)
sketch "07 - GNSS Power LED Sketch" plane through (0, 0, 32.1) normal (0, 0, 1) x (1, 0, 0)
  line L0 (-2, -20.5) -> (0, -20.5)
  line L1 (0, -20.5) -> (0, -18.5)
  line L2 (0, -18.5) -> (-2, -18.5)
  line L3 (-2, -18.5) -> (-2, -20.5)
extrude "07 - GNSS Power LED" add sketch "07 - GNSS Power LED Sketch" along normal blind 1.2 separate body makes body 14
ref_plane "WorkPlane55" through (0, 0, 32.1) normal (0, 0, 1) x (1, 0, 0)
sketch "08 - GNSS Support IC Sketch" plane through (0, 0, 32.1) normal (0, 0, 1) x (1, 0, 0)
  line L0 (-7, -29) -> (-3, -29)
  line L1 (-3, -29) -> (-3, -26)
  line L2 (-3, -26) -> (-7, -26)
  line L3 (-7, -26) -> (-7, -29)
extrude "08 - GNSS Support IC" add sketch "08 - GNSS Support IC Sketch" along normal blind 1 separate body makes body 15
ref_plane "WorkPlane56" through (0, 0, 32.1) normal (0, 0, 1) x (1, 0, 0)
sketch "09 - GNSS SMD 01 Sketch" plane through (0, 0, 32.1) normal (0, 0, 1) x (1, 0, 0)
  line L0 (-6, -18) -> (-3.5, -18)
  line L1 (-3.5, -18) -> (-3.5, -16.5)
  line L2 (-3.5, -16.5) -> (-6, -16.5)
  line L3 (-6, -16.5) -> (-6, -18)
extrude "09 - GNSS SMD 01" add sketch "09 - GNSS SMD 01 Sketch" along normal blind 0.7 separate body makes body 16
ref_plane "WorkPlane57" through (0, 0, 32.1) normal (0, 0, 1) x (1, 0, 0)
sketch "09 - GNSS SMD 02 Sketch" plane through (0, 0, 32.1) normal (0, 0, 1) x (1, 0, 0)
  line L0 (-1, -18) -> (1.5, -18)
  line L1 (1.5, -18) -> (1.5, -16.5)
  line L2 (1.5, -16.5) -> (-1, -16.5)
  line L3 (-1, -16.5) -> (-1, -18)
extrude "09 - GNSS SMD 02" add sketch "09 - GNSS SMD 02 Sketch" along normal blind 0.7 separate body makes body 17
ref_plane "WorkPlane58" through (0, 0, 32.1) normal (0, 0, 1) x (1, 0, 0)
sketch "09 - GNSS SMD 03 Sketch" plane through (0, 0, 32.1) normal (0, 0, 1) x (1, 0, 0)
  line L0 (5, -18) -> (7.5, -18)
  line L1 (7.5, -18) -> (7.5, -16.5)
  line L2 (7.5, -16.5) -> (5, -16.5)
  line L3 (5, -16.5) -> (5, -18)
extrude "09 - GNSS SMD 03" add sketch "09 - GNSS SMD 03 Sketch" along normal blind 0.7 separate body makes body 18
ref_plane "WorkPlane59" through (0, 0, 32.1) normal (0, 0, 1) x (1, 0, 0)
sketch "09 - GNSS SMD 04 Sketch" plane through (0, 0, 32.1) normal (0, 0, 1) x (1, 0, 0)
  line L0 (10, -18) -> (12.5, -18)
  line L1 (12.5, -18) -> (12.5, -16.5)
  line L2 (12.5, -16.5) -> (10, -16.5)
  line L3 (10, -16.5) -> (10, -18)
extrude "09 - GNSS SMD 04" add sketch "09 - GNSS SMD 04 Sketch" along normal blind 0.7 separate body makes body 19
ref_plane "WorkPlane60" through (0, 0, 32.2) normal (0, 0, 1) x (1, 0, 0)
sketch "10 - GNSS Antenna Keep-Out Sketch" plane through (0, 0, 32.2) normal (0, 0, 1) x (1, 0, 0)
  line L0 (-8, -34) -> (-4, -34)
  line L1 (-4, -34) -> (-4, -26)
  line L2 (-4, -26) -> (-8, -26)
  line L3 (-8, -26) -> (-8, -34)
extrude "10 - GNSS Antenna Keep-Out" add sketch "10 - GNSS Antenna Keep-Out Sketch" along normal blind 0.3 separate body makes body 20
